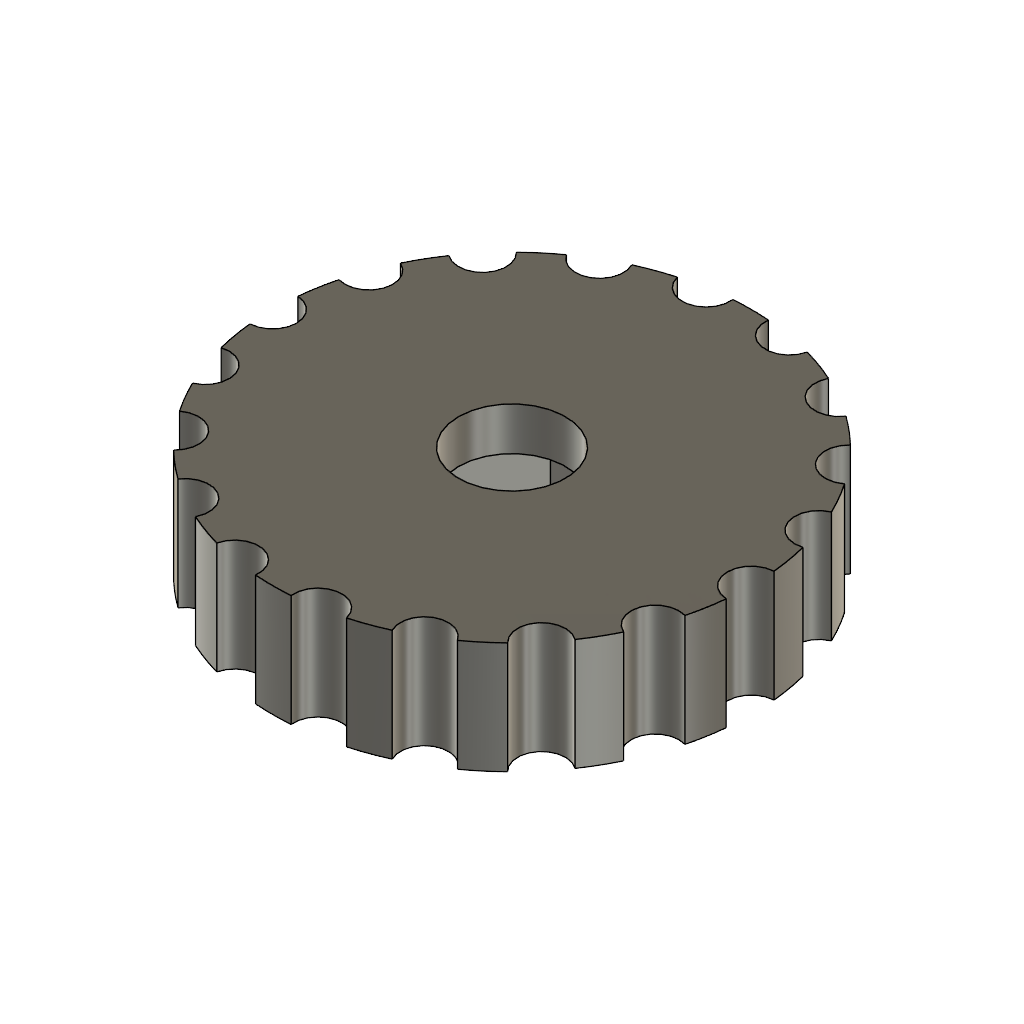
DSLR_Thumbwheel (Autodesk Fusion 360 design; units mm, degrees)
part number: 2026-10-19-10-28-44-568
Autodesk Fusion 360 part; units mm, degrees
sketch "wheel" plane through (0, 0, 0) normal (0, 0, 1) x (1, 0, 0)
  circle A0 centre (0, 125) radius 15
extrude "wheel (1)" add sketch "wheel" along normal blind 7 from surface at 174.4
sketch "knurl" plane through (0, 0, 0) normal (0, 0, 1) x (1, 0, 0)
  circle A0 centre (15, 125) radius 1.5
  circle A1 centre (14.0954, 130.1303) radius 1.5
  circle A2 centre (11.4907, 134.6418) radius 1.5
  circle A3 centre (7.5, 137.9904) radius 1.5
  circle A4 centre (2.6047, 139.7721) radius 1.5
  circle A5 centre (-2.6047, 139.7721) radius 1.5
  circle A6 centre (-7.5, 137.9904) radius 1.5
  circle A7 centre (-11.4907, 134.6418) radius 1.5
  circle A8 centre (-14.0954, 130.1303) radius 1.5
  circle A9 centre (-15, 125) radius 1.5
  circle A10 centre (-14.0954, 119.8697) radius 1.5
  circle A11 centre (-11.4907, 115.3582) radius 1.5
  circle A12 centre (-7.5, 112.0096) radius 1.5
  circle A13 centre (-2.6047, 110.2279) radius 1.5
  circle A14 centre (2.6047, 110.2279) radius 1.5
  circle A15 centre (7.5, 112.0096) radius 1.5
  circle A16 centre (11.4907, 115.3582) radius 1.5
  circle A17 centre (14.0954, 119.8697) radius 1.5
extrude "knurl (1)" cut sketch "knurl" along normal blind 8 from surface at 173.9
sketch "hex_pocket" plane through (0, 0, 0) normal (0, 0, 1) x (1, 0, 0)
  line L0 (6.5818, 125) -> (3.2909, 130.7)
  line L1 (3.2909, 130.7) -> (-3.2909, 130.7)
  line L2 (-3.2909, 130.7) -> (-6.5818, 125)
  line L3 (-6.5818, 125) -> (-3.2909, 119.3)
  line L4 (-3.2909, 119.3) -> (3.2909, 119.3)
  line L5 (3.2909, 119.3) -> (6.5818, 125)
extrude "hex_pocket (1)" cut sketch "hex_pocket" along normal blind 4.8 from surface at 173.9
sketch "bolt_hole" plane through (0, 0, 0) normal (0, 0, 1) x (1, 0, 0)
  circle A0 centre (0, 125) radius 3.35
extrude "bolt_hole (1)" cut sketch "bolt_hole" along normal blind 8 from surface at 173.9
named bodies: "DSLR Thumbwheel"
